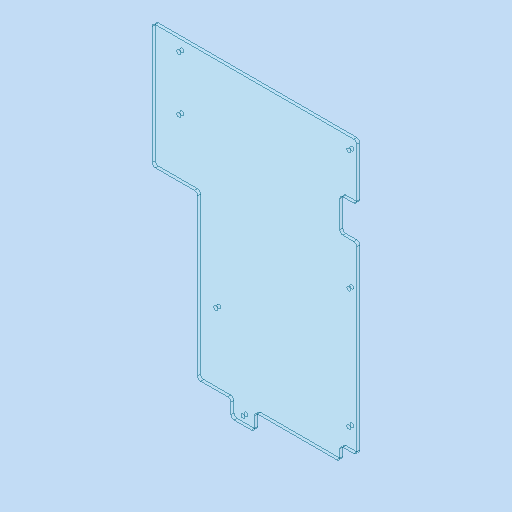
# Autodesk Inventor part: MM0948AN140_G01_112
Saved by Autodesk Inventor 2023.3 (Build 273359000, 359)
## iProperties
Created: 2023-03-23
Part Number: MM0948AN140_G01_112
Material: Kst - PC (Eslon, klar)
Description: =<RBPARTNOTITLE2>
Document SubType Name: Modeling
Designer: ric7an
Mass: 830.526 g
Surface Area: 2860.66 cm^2
Volume: 692.105 cm^3
Density: 1.2 g/cm^3
Appearance: Klar AnP
AnP_Kategorie: 1
AnP_Material: =<Material>
MaxAbmaße: 5 x 503 x 338 (FM)
AnP_TemplVers: 20200821
RBDOCUMENTTYPE: DRF
RBDOCUMENTVERSION: 00
RBDRAWINGMAINSCALE: 1:1
RBDRAWINGMISSINGSPEC: --
RBDRAWINGVOLUME: --
RBDSV1: 0850
RBGBEDGESIN1: +0,5
RBGBEDGESIN2: +0,2
RBGBEDGESOUT1: -0,3
RBGBEDGESOUT2: -0,1
RBMATERIAL: =<Material>
RBMATMEETS: --
RBMATNO: =<Part Number>
RBPARTMADEOF: 5 x 503 x 338 (FM)
RBPARTNO: SIEHE MNR
RBPARTNOTITLE1: manufactured part
RBPARTNOTITLE2: Anfertigungsteil
RBPARTSAFETYINDICATOR: --
RBSURFACE: --
RBSURFACE2: --
RBZEDGESNORM: ISO13715:2002-06
RBZGENDIMCLASS: m
RBZGENDIMNORM: ISO 2768-1:1989-11
RBZGENGEOCLASS: H
RBZGENGEONORM: ISO 2768-2:1989-11
RBZSURFACENORM: ISO13D2:2002-02
RBZTOLERANCENORM: ISO 14405-1:2010-12
AnP_Kommentar_aktuell: =<Comments>
AnP_Material_aktuell: =<Material>
Author: FH/Wi
Keywords: =<RBPARTMADEOF>
Comments: =<RBSURFACE2>
Revision Number: 01
Autodesk Inventor part; units mm, degrees
ref_plane "YZ Plane" through (0, 0, 0) normal (1, 0, 0) x (0, 1, 0)
ref_plane "XZ Plane" through (0, 0, 0) normal (0, 1, 0) x (-1, 0, 0)
ref_plane "XY Plane" through (0, 0, 0) normal (0, 0, 1) x (1, 0, 0)
sketch "Skizze1" plane through (0, 0, 0) normal (0, 0, 1) x (1, 0, 0)
  line L0 (-169, 473) -> (169, 473)
  line L1 (169, 473) -> (169, 0)
  line L2 (169, 0) -> (-169, 0)
  line L3 (-169, 0) -> (-169, 473)
  line L4 (0, 573.2) -> (0, -128.2) projected
  line L5 (-236.6, 0) -> (236.6, 0) projected
  line L6 (-169, 0) -> (-94, 0)
  line L7 (-94, 0) -> (-94, 268)
  line L8 (-94, 268) -> (-169, 268)
  line L9 (-169, 268) -> (-169, 0)
  line L10 (-39, 0) -> (1, 0)
  line L11 (1, 0) -> (1, -28)
  line L12 (1, -28) -> (-39, -28)
  line L13 (-39, -28) -> (-39, 0)
  line L14 (169, 381.5) -> (141, 381.5)
  line L15 (141, 381.5) -> (141, 326.5)
  line L16 (141, 326.5) -> (169, 326.5)
  line L17 (169, 326.5) -> (169, 381.5)
  line L18 (169, 0) -> (141, 0)
  line L19 (141, 0) -> (141, 23)
  line L20 (141, 23) -> (169, 23)
  line L21 (169, 23) -> (169, 0)
  point P0 (0, 0)
  point P1 (-94, 0)
  point P2 (-39, 0)
  point P3 (0, -28)
  point P4 (0, 0)
  point P5 (141, 354)
  point P6 (169, 326.5)
  point P7 (169, 23)
  dimension "d0" = 338
  dimension "d1" = 473
  dimension "d4" = 205
  dimension "d5" = 75
  dimension "d26" = 55
  dimension "d27" = 40
  dimension "d28" = 28
  dimension "d31" = 119
  dimension "d32" = 55
  dimension "d33" = 28
  dimension "d34" = 23
  constraints: 40 end point, 10 parallel, 5 horizontal, 5 perpendicular, 2 collinear, 2 point on line, 1 midpoint, 1 other
  measures "d0" distance of L0.start L0.end
  measures "d1" distance of L0.end L1.end
  measures "d4" distance between parallel lines of L8 L0
  measures "d5" distance of L7.end L8.end
  measures "d26" distance between parallel lines of L13 L7
  measures "d27" distance of L11.end L12.end
  measures "d28" distance of L12.end L10.start
  measures "d31" distance from line of L0 point (141, 354)
  measures "d32" distance of L14.end L15.end
  measures "d33" distance of L14.start L14.end
  measures "d34" distance of L18.end L19.end
extrude "Extrusion1" add sketch "Skizze1" along normal blind 5 contours L0 L4 L2 L7 L8 L3 | L0 L1 L14 L15 L16 L20 L19 L2 L4 | L4 L12 L13 L2
sketch "Skizze2" plane through (0, 0, 5) normal (0, 0, 1) x (1, 0, 0)
  line L0 (-169, 473) -> (-169, 268) projected
  line L1 (169, 473) -> (-169, 473) projected
  line L2 (-169, 268) -> (-94, 268) projected
  line L3 (156, 453) -> (156, 57)
  line L4 (-94, 0) -> (-39, 0) projected
  line L5 (-94, 268) -> (-94, 0) projected
  line L6 (169, 381.5) -> (169, 473) projected
  line L7 (-39, -28) -> (0, -28) projected
  line L8 (-39, 0) -> (-39, -28) projected
  point P0 (0, 0)
  point P1 (-125, 453)
  point P2 (-125, 363)
  point P3 (156, 255)
  point P4 (-64, 117)
  point P5 (169, 0)
  point P6 (156, 255)
  point P7 (-19, -15)
  dimension "d13" = 44
  dimension "d14" = 20
  dimension "d16" = 117
  dimension "d17" = 30
  dimension "d18" = 13
  dimension "d29" = 13
  dimension "d30" = 20
  dimension "d35" = 90
  dimension "d36" = 198
  constraints: 2 end point, 2 vertical alignment, 1 coincident, 1 horizontal alignment, 1 midpoint, 1 vertical
  measures "d13" distance from line of point (-125, 453) L0
  measures "d14" distance from line of point (-125, 453) L1
  measures "d16" distance from line of L4 point (-64, 117)
  measures "d17" distance from line of point (-64, 117) L5
  measures "d18" distance between parallel lines of L6 L3
  measures "d29" distance from line of L7 point (-19, -15)
  measures "d30" distance from line of point (-19, -15) L8
  measures "d35" distance of point (-125, 363) point (-125, 453)
  measures "d36" distance of point (156, 255) L3.start
hole "Bohrung1" at (-125, 453, 5) at (-125, 363, 5) at (156, 57, 5) at (156, 255, 5) at (-64, 117, 5) at (156, 453, 5) at (-19, -15, 5) direction (0, 0, -1) diameter 6.6 end through all clearance for "Inbusschraube ISO 4762  versenkt" size "M6" standard "ISO"
fillet "Rundung1" radius 5 16 edges at (-94, 0, 2.5) (-39, 0, 2.5) (-39, -28, 2.5) (0, -28, 2.5) (0, 0, 2.5) (-94, 268, 2.5) (-169, 268, 2.5) (-169, 473, 2.5) (169, 473, 2.5) (169, 381.5, 2.5) (141, 381.5, 2.5) (141, 326.5, 2.5) (169, 326.5, 2.5) (169, 23, 2.5) (141, 23, 2.5) (141, 0, 2.5)
